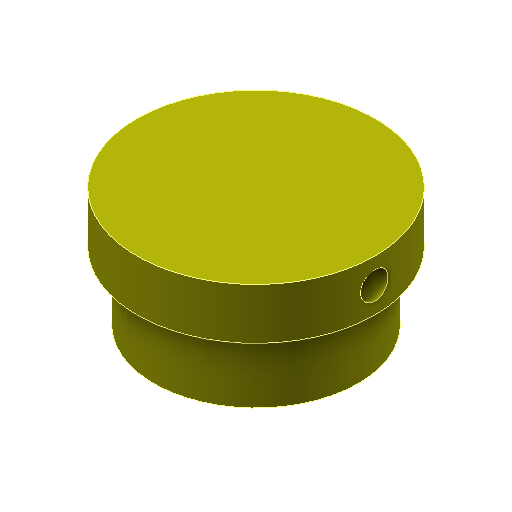
# Autodesk Inventor part: OT2-Pipette V0.3 - spring pad
Saved by Autodesk Inventor 2025.5 (Build 295498000, 498)
## iProperties
Created: 2026-11-01
Part Number: OT2-Pipette V0.3 - spring pad
Material: Generisch
Description: printed spring pad, eject variant (2 M2 pins in the skirt slots)
Document SubType Name: Modeling
Designer: benir
Density: 1 g/cm^3
Appearance: Yellow
Author: benir
Autodesk Inventor part; units mm, degrees
ref_plane "y=pad_face" through (0, 74, 0) normal (0, 1, 0) x (-1, 0, 0)
sketch "nose" plane through (0, 74, 0) normal (0, 1, 0) x (-1, 0, 0)
  circle A0 centre (-8.2, -3.46) radius 6
  point P0 (0, 0)
  dimension "d3" = 3.46
  dimension "d4" = 8.2
  dimension "d5" = 12
  constraints: 1 centre point
  measures "d3" vertical distance of point (0, 0) A0.centre
  measures "d4" horizontal distance of point (0, 0) A0.centre
  measures "d5" diameter of A0
extrude "Extrusion2" add sketch "nose" along normal blind 4
ref_plane "y=skirt_y0 + flange_gap" through (0, 78, 0) normal (0, 1, 0) x (-1, 0, 0)
sketch "flange" plane through (0, 78, 0) normal (0, 1, 0) x (-1, 0, 0)
  circle A0 centre (-8.2, -3.46) radius 7
  point P0 (0, 0)
  dimension "d9" = 3.46
  dimension "d10" = 8.2
  dimension "d11" = 14
  constraints: 1 centre point
  measures "d9" vertical distance of point (0, 0) A0.centre
  measures "d10" horizontal distance of point (0, 0) A0.centre
  measures "d11" diameter of A0
extrude "Extrusion3" add sketch "flange" along normal blind 3
ref_plane "x=pip_x - slot_half_len" through (-1.8, 0, 0) normal (1, 0, 0) x (0, 1, 0)
sketch "pin hole" plane through (-1.8, 0, 0) normal (1, 0, 0) x (0, 1, 0)
  circle A0 centre (79.5, -3.46) radius 0.8
  point P0 (0, 0)
  dimension "d15" = 3.46
  dimension "d16" = 79.5
  dimension "d17" = 1.6
  constraints: 1 centre point
  measures "d15" vertical distance of point (0, 0) A0.centre
  measures "d16" horizontal distance of point (0, 0) A0.centre
  measures "d17" diameter of A0
extrude "M2 pin hole" cut sketch "pin hole" along normal blind 20
equation "\"d3\" = -pip_z"
equation "\"d4\" = pip_x"
equation "\"d5\" = nose_d"
equation "\"d6\" = flange_gap + skirt_y0 - pad_face"
equation "\"d9\" = -pip_z"
equation "\"d10\" = pip_x"
equation "\"d11\" = flange_d"
equation "\"d12\" = flange_h"
equation "\"d15\" = -pip_z"
equation "\"d16\" = skirt_y0 + pin_y"
equation "\"d17\" = pin_d"
equation "\"d18\" = 2 * slot_half_len"
equation "\"nose_d\" = 12"
equation "\"flange_gap\" = 1"
equation "\"skirt_y0\" = 77"
equation "\"pad_face\" = 74"
equation "\"flange_d\" = 14"
equation "\"flange_h\" = 3"
equation "\"pin_d\" = 1.6"
equation "\"slot_half_len\" = 10"
equation "\"pip_z\" = -3.46"
equation "\"pip_x\" = 8.2"
equation "\"pin_y\" = 2.5"
body "Solid2"
